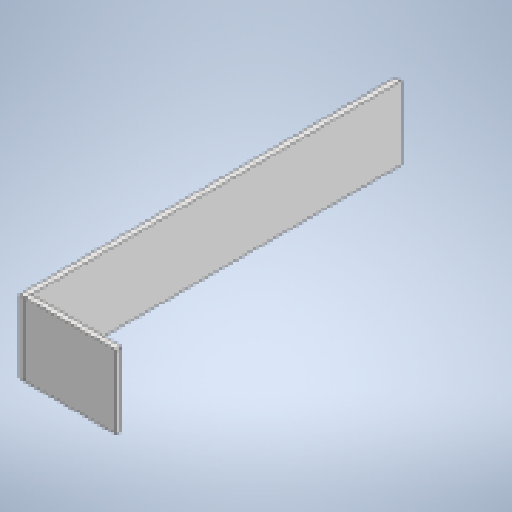
# Autodesk Inventor part: PRF-0001 Room
Saved by Autodesk Inventor 2026.2 (Build 302298000, 298)
## iProperties
Created: 2026-10-18
Part Number: PRF-0001 Room
Material: Generic
Description: Reagent room, rough: plan sketch, each wall = separate body (as Workshop sample Wall 5), ceiling body; sizes to confirm
Document SubType Name: Modeling
Designer: admin
Stock Number: Помещение реагентного хозяйства (примерно, по фото)
Density: 1 g/cm^3
Appearance: Default
Author: admin
Autodesk Inventor part; units mm, degrees
ref_plane "YZ Plane" through (0, 0, 0) normal (1, 0, 0) x (0, 1, 0)
ref_plane "XZ Plane" through (0, 0, 0) normal (0, 1, 0) x (-1, 0, 0)
ref_plane "XY Plane" through (0, 0, 0) normal (0, 0, 1) x (1, 0, 0)
sketch "Plan" plane through (0, 0, 0) normal (0, 1, 0) x (-1, 0, 0)
  line L0 (2250, -8250) -> (2000, -8250)
  line L1 (2000, -8250) -> (2000, 8250)
  line L2 (2000, 8250) -> (2250, 8250)
  line L3 (2250, 8250) -> (2250, -8250)
  line L4 (-2000, -8250) -> (-2250, -8250)
  line L5 (-2250, -8250) -> (-2250, 8250)
  line L6 (-2250, 8250) -> (-2000, 8250)
  line L7 (-2000, 8250) -> (-2000, -8250)
  line L8 (2000, -8250) -> (-2000, -8250)
  line L9 (-2000, -8250) -> (-2000, -8000)
  line L10 (-2000, -8000) -> (2000, -8000)
  line L11 (2000, -8000) -> (2000, -8250)
  line L12 (2000, 8000) -> (-2000, 8000)
  line L13 (-2000, 8000) -> (-2000, 8250)
  line L14 (-2000, 8250) -> (2000, 8250)
  line L15 (2000, 8250) -> (2000, 8000)
  constraints: 32 end point, 8 parallel, 4 horizontal, 4 perpendicular
extrude "Wall Left" add sketch "Plan" along normal blind 3200 contours L0 L1 L2 L3
extrude "Wall Right" add sketch "Plan" along normal blind 3200 separate body contours L4 L5 L6 L7
extrude "Wall Front" add sketch "Plan" along normal blind 3200 separate body contours L8 L7 L10 L1
extrude "Wall Back" add sketch "Plan" along normal blind 3200 separate body contours L1 L12 L7 L14
sketch "Ceiling Sketch" plane through (0, 3200, 0) normal (0, 1, 0) x (1, 0, 0)
  line L0 (-2250, 8250) -> (2250, 8250)
  line L1 (2250, 8250) -> (2250, -8250)
  line L2 (2250, -8250) -> (-2250, -8250)
  line L3 (-2250, -8250) -> (-2250, 8250)
  constraints: 8 end point, 2 parallel, 1 horizontal, 1 perpendicular
extrude "Ceiling" [suppressed]
equation "\"d14\" = Room0001_Height"
equation "\"d16\" = Room0001_Height"
equation "\"d18\" = Room0001_Height"
equation "\"d20\" = Room0001_Height"
equation "\"d22\" = Room0001_Ceiling_Thickness"
equation "\"Room0001_Height\" = 3200"
equation "\"Room0001_Ceiling_Thickness\" = 200"
body "Solid3"
body "Solid4"
body "Solid5"
body "Solid6"
body "Solid7"
